Autodesk Fusion 360 part; units mm, degrees
(part 2 of 2)
  line L933 (25.5948, 17.0334) -> (24.794, 17.0334)
  line L934 (24.794, 17.0334) -> (24.794, 22.8334)
  line L935 (24.794, 22.8334) -> (25.5948, 22.8334)
  line L936 (25.5948, 22.8334) -> (25.5948, 25.9326)
  line L937 (25.5948, 25.9326) -> (24.794, 25.9326)
  line L938 (24.794, 25.9326) -> (24.794, 26.9331)
  line L939 (24.794, 26.9331) -> (10.7947, 26.9331)
  line L940 (29.8447, 26.9331) -> (29.8447, 25.9326)
  line L941 (29.8447, 25.9326) -> (29.0439, 25.9326)
  line L942 (29.0439, 25.9326) -> (29.0439, 22.8334)
  line L943 (29.0439, 22.8334) -> (29.8447, 22.8334)
  line L944 (29.8447, 22.8334) -> (29.8447, 17.0334)
  line L945 (29.8447, 17.0334) -> (29.0439, 17.0334)
  line L946 (29.0439, 17.0334) -> (29.0439, 13.9328)
  line L947 (29.0439, 13.9328) -> (29.8447, 13.9328)
  line L948 (29.8447, 13.9328) -> (29.8447, 12.9338)
  line L949 (29.8447, 12.9338) -> (43.844, 12.9338)
  line L950 (43.844, 12.9338) -> (43.844, 13.9328)
  line L951 (43.844, 13.9328) -> (44.645, 13.9328)
  line L952 (44.645, 13.9328) -> (44.645, 17.0334)
  line L953 (44.645, 17.0334) -> (43.844, 17.0334)
  line L954 (43.844, 17.0334) -> (43.844, 22.8334)
  line L955 (43.844, 22.8334) -> (44.645, 22.8334)
  line L956 (44.645, 22.8334) -> (44.645, 25.9326)
  line L957 (44.645, 25.9326) -> (43.844, 25.9326)
  line L958 (43.844, 25.9326) -> (43.844, 26.9331)
  line L959 (43.844, 26.9331) -> (29.8447, 26.9331)
  line L960 (48.895, 26.9331) -> (48.895, 25.9326)
  line L961 (48.895, 25.9326) -> (48.094, 25.9326)
  line L962 (48.094, 25.9326) -> (48.094, 22.8334)
  line L963 (48.094, 22.8334) -> (48.895, 22.8334)
  line L964 (48.895, 22.8334) -> (48.895, 17.0334)
  line L965 (48.895, 17.0334) -> (48.094, 17.0334)
  line L966 (48.094, 17.0334) -> (48.094, 13.9328)
  line L967 (48.094, 13.9328) -> (48.895, 13.9328)
  line L968 (48.895, 13.9328) -> (48.895, 12.9338)
  line L969 (48.895, 12.9338) -> (62.894, 12.9338)
  line L970 (62.894, 12.9338) -> (62.894, 13.9328)
  line L971 (62.894, 13.9328) -> (63.695, 13.9328)
  line L972 (63.695, 13.9328) -> (63.695, 17.0334)
  line L973 (63.695, 17.0334) -> (62.894, 17.0334)
  line L974 (62.894, 17.0334) -> (62.894, 22.8334)
  line L975 (62.894, 22.8334) -> (63.695, 22.8334)
  line L976 (63.695, 22.8334) -> (63.695, 25.9326)
  line L977 (63.695, 25.9326) -> (62.894, 25.9326)
  line L978 (62.894, 25.9326) -> (62.894, 26.9331)
  line L979 (62.894, 26.9331) -> (48.895, 26.9331)
  line L980 (67.945, 26.9331) -> (67.945, 25.9326)
  line L981 (67.945, 25.9326) -> (67.144, 25.9326)
  line L982 (67.144, 25.9326) -> (67.144, 22.8334)
  line L983 (67.144, 22.8334) -> (67.945, 22.8334)
  line L984 (67.945, 22.8334) -> (67.945, 17.0334)
  line L985 (67.945, 17.0334) -> (67.144, 17.0334)
  line L986 (67.144, 17.0334) -> (67.144, 13.9328)
  line L987 (67.144, 13.9328) -> (67.945, 13.9328)
  line L988 (67.945, 13.9328) -> (67.945, 12.9338)
  line L989 (67.945, 12.9338) -> (81.944, 12.9338)
  line L990 (81.944, 12.9338) -> (81.944, 13.9328)
  line L991 (81.944, 13.9328) -> (82.745, 13.9328)
  line L992 (82.745, 13.9328) -> (82.745, 17.0334)
  line L993 (82.745, 17.0334) -> (81.944, 17.0334)
  line L994 (81.944, 17.0334) -> (81.944, 22.8334)
  line L995 (81.944, 22.8334) -> (82.745, 22.8334)
  line L996 (82.745, 22.8334) -> (82.745, 25.9326)
  line L997 (82.745, 25.9326) -> (81.944, 25.9326)
  line L998 (81.944, 25.9326) -> (81.944, 26.9331)
  line L999 (81.944, 26.9331) -> (67.945, 26.9331)
  line L1000 (86.995, 26.9331) -> (86.995, 25.9326)
  line L1001 (86.995, 25.9326) -> (86.194, 25.9326)
  line L1002 (86.194, 25.9326) -> (86.194, 22.8334)
  line L1003 (86.194, 22.8334) -> (86.995, 22.8334)
  line L1004 (86.995, 22.8334) -> (86.995, 17.0334)
  line L1005 (86.995, 17.0334) -> (86.194, 17.0334)
  line L1006 (86.194, 17.0334) -> (86.194, 13.9328)
  line L1007 (86.194, 13.9328) -> (86.995, 13.9328)
  line L1008 (86.995, 13.9328) -> (86.995, 12.9338)
  line L1009 (86.995, 12.9338) -> (100.994, 12.9338)
  line L1010 (100.994, 12.9338) -> (100.994, 13.9328)
  line L1011 (100.994, 13.9328) -> (101.795, 13.9328)
  line L1012 (101.795, 13.9328) -> (101.795, 17.0334)
  line L1013 (101.795, 17.0334) -> (100.994, 17.0334)
  line L1014 (100.994, 17.0334) -> (100.994, 22.8334)
  line L1015 (100.994, 22.8334) -> (101.795, 22.8334)
  line L1016 (101.795, 22.8334) -> (101.795, 25.9326)
  line L1017 (101.795, 25.9326) -> (100.994, 25.9326)
  line L1018 (100.994, 25.9326) -> (100.994, 26.9331)
  line L1019 (100.994, 26.9331) -> (86.995, 26.9331)
  line L1020 (106.045, 26.9331) -> (106.045, 25.9326)
  line L1021 (106.045, 25.9326) -> (105.244, 25.9326)
  line L1022 (105.244, 25.9326) -> (105.244, 22.8334)
  line L1023 (105.244, 22.8334) -> (106.045, 22.8334)
  line L1024 (106.045, 22.8334) -> (106.045, 17.0334)
  line L1025 (106.045, 17.0334) -> (105.244, 17.0334)
  line L1026 (105.244, 17.0334) -> (105.244, 13.9328)
  line L1027 (105.244, 13.9328) -> (106.045, 13.9328)
  line L1028 (106.045, 13.9328) -> (106.045, 12.9338)
  line L1029 (106.045, 12.9338) -> (120.044, 12.9338)
  line L1030 (120.044, 12.9338) -> (120.044, 13.9328)
  line L1031 (120.044, 13.9328) -> (120.845, 13.9328)
  line L1032 (120.845, 13.9328) -> (120.845, 17.0334)
  line L1033 (120.845, 17.0334) -> (120.044, 17.0334)
  line L1034 (120.044, 17.0334) -> (120.044, 22.8334)
  line L1035 (120.044, 22.8334) -> (120.845, 22.8334)
  line L1036 (120.845, 22.8334) -> (120.845, 25.9326)
  line L1037 (120.845, 25.9326) -> (120.044, 25.9326)
  line L1038 (120.044, 25.9326) -> (120.044, 26.9331)
  line L1039 (120.044, 26.9331) -> (106.045, 26.9331)
  line L1040 (125.095, 26.9331) -> (125.095, 25.9326)
  line L1041 (125.095, 25.9326) -> (124.294, 25.9326)
  line L1042 (124.294, 25.9326) -> (124.294, 22.8334)
  line L1043 (124.294, 22.8334) -> (125.095, 22.8334)
  line L1044 (125.095, 22.8334) -> (125.095, 17.0334)
  line L1045 (125.095, 17.0334) -> (124.294, 17.0334)
  line L1046 (124.294, 17.0334) -> (124.294, 13.9328)
  line L1047 (124.294, 13.9328) -> (125.095, 13.9328)
  line L1048 (125.095, 13.9328) -> (125.095, 12.9338)
  line L1049 (125.095, 12.9338) -> (139.094, 12.9338)
  line L1050 (139.094, 12.9338) -> (139.094, 13.9328)
  line L1051 (139.094, 13.9328) -> (139.895, 13.9328)
  line L1052 (139.895, 13.9328) -> (139.895, 17.0334)
  line L1053 (139.895, 17.0334) -> (139.094, 17.0334)
  line L1054 (139.094, 17.0334) -> (139.094, 22.8334)
  line L1055 (139.094, 22.8334) -> (139.895, 22.8334)
  line L1056 (139.895, 22.8334) -> (139.895, 25.9326)
  line L1057 (139.895, 25.9326) -> (139.094, 25.9326)
  line L1058 (139.094, 25.9326) -> (139.094, 26.9331)
  line L1059 (139.094, 26.9331) -> (125.095, 26.9331)
  line L1060 (144.145, 26.9331) -> (144.145, 25.9326)
  line L1061 (144.145, 25.9326) -> (143.344, 25.9326)
  line L1062 (143.344, 25.9326) -> (143.344, 22.8334)
  line L1063 (143.344, 22.8334) -> (144.145, 22.8334)
  line L1064 (144.145, 22.8334) -> (144.145, 17.0334)
  line L1065 (144.145, 17.0334) -> (143.344, 17.0334)
  line L1066 (143.344, 17.0334) -> (143.344, 13.9328)
  line L1067 (143.344, 13.9328) -> (144.145, 13.9328)
  line L1068 (144.145, 13.9328) -> (144.145, 12.9338)
  line L1069 (144.145, 12.9338) -> (158.144, 12.9338)
  line L1070 (158.144, 12.9338) -> (158.144, 13.9328)
  line L1071 (158.144, 13.9328) -> (158.945, 13.9328)
  line L1072 (158.945, 13.9328) -> (158.945, 17.0334)
  line L1073 (158.945, 17.0334) -> (158.144, 17.0334)
  line L1074 (158.144, 17.0334) -> (158.144, 22.8334)
  line L1075 (158.144, 22.8334) -> (158.945, 22.8334)
  line L1076 (158.945, 22.8334) -> (158.945, 25.9326)
  line L1077 (158.945, 25.9326) -> (158.144, 25.9326)
  line L1078 (158.144, 25.9326) -> (158.144, 26.9331)
  line L1079 (158.144, 26.9331) -> (144.145, 26.9331)
  line L1080 (163.195, 26.9331) -> (163.195, 25.9326)
  line L1081 (163.195, 25.9326) -> (162.394, 25.9326)
  line L1082 (162.394, 25.9326) -> (162.394, 22.8334)
  line L1083 (162.394, 22.8334) -> (163.195, 22.8334)
  line L1084 (163.195, 22.8334) -> (163.195, 17.0334)
  line L1085 (163.195, 17.0334) -> (162.394, 17.0334)
  line L1086 (162.394, 17.0334) -> (162.394, 13.9328)
  line L1087 (162.394, 13.9328) -> (163.195, 13.9328)
  line L1088 (163.195, 13.9328) -> (163.195, 12.9338)
  line L1089 (163.195, 12.9338) -> (177.194, 12.9338)
  line L1090 (177.194, 12.9338) -> (177.194, 13.9328)
  line L1091 (177.194, 13.9328) -> (177.995, 13.9328)
  line L1092 (177.995, 13.9328) -> (177.995, 17.0334)
  line L1093 (177.995, 17.0334) -> (177.194, 17.0334)
  line L1094 (177.194, 17.0334) -> (177.194, 22.8334)
  line L1095 (177.194, 22.8334) -> (177.995, 22.8334)
  line L1096 (177.995, 22.8334) -> (177.995, 25.9326)
  line L1097 (177.995, 25.9326) -> (177.194, 25.9326)
  line L1098 (177.194, 25.9326) -> (177.194, 26.9331)
  line L1099 (177.194, 26.9331) -> (163.195, 26.9331)
  line L1100 (182.245, 26.9331) -> (182.245, 25.9326)
  line L1101 (182.245, 25.9326) -> (181.444, 25.9326)
  line L1102 (181.444, 25.9326) -> (181.444, 22.8334)
  line L1103 (181.444, 22.8334) -> (182.245, 22.8334)
  line L1104 (182.245, 22.8334) -> (182.245, 17.0334)
  line L1105 (182.245, 17.0334) -> (181.444, 17.0334)
  line L1106 (181.444, 17.0334) -> (181.444, 13.9328)
  line L1107 (181.444, 13.9328) -> (182.245, 13.9328)
  line L1108 (182.245, 13.9328) -> (182.245, 12.9338)
  line L1109 (182.245, 12.9338) -> (196.244, 12.9338)
  line L1110 (196.244, 12.9338) -> (196.244, 13.9328)
  line L1111 (196.244, 13.9328) -> (197.045, 13.9328)
  line L1112 (197.045, 13.9328) -> (197.045, 17.0334)
  line L1113 (197.045, 17.0334) -> (196.244, 17.0334)
  line L1114 (196.244, 17.0334) -> (196.244, 22.8334)
  line L1115 (196.244, 22.8334) -> (197.045, 22.8334)
  line L1116 (197.045, 22.8334) -> (197.045, 25.9326)
  line L1117 (197.045, 25.9326) -> (196.244, 25.9326)
  line L1118 (196.244, 25.9326) -> (196.244, 26.9331)
  line L1119 (196.244, 26.9331) -> (182.245, 26.9331)
  line L1120 (206.057, 26.9331) -> (206.057, 25.9326)
  line L1121 (206.057, 25.9326) -> (205.256, 25.9326)
  line L1122 (205.256, 25.9326) -> (205.256, 22.8334)
  line L1123 (205.256, 22.8334) -> (206.057, 22.8334)
  line L1124 (206.057, 22.8334) -> (206.057, 17.0334)
  line L1125 (206.057, 17.0334) -> (205.256, 17.0334)
  line L1126 (205.256, 17.0334) -> (205.256, 13.9328)
  line L1127 (205.256, 13.9328) -> (206.057, 13.9328)
  line L1128 (206.057, 13.9328) -> (206.057, 12.9338)
  line L1129 (206.057, 12.9338) -> (220.057, 12.9338)
  line L1130 (220.057, 12.9338) -> (220.057, 13.9328)
  line L1131 (220.057, 13.9328) -> (220.856, 13.9328)
  line L1132 (220.856, 13.9328) -> (220.856, 17.0334)
  line L1133 (220.856, 17.0334) -> (220.057, 17.0334)
  line L1134 (220.057, 17.0334) -> (220.057, 22.8334)
  line L1135 (220.057, 22.8334) -> (220.856, 22.8334)
  line L1136 (220.856, 22.8334) -> (220.856, 25.9326)
  line L1137 (220.856, 25.9326) -> (220.057, 25.9326)
  line L1138 (220.057, 25.9326) -> (220.057, 26.9331)
  line L1139 (220.057, 26.9331) -> (206.057, 26.9331)
  line L1140 (229.87, 26.9331) -> (229.87, 25.9326)
  line L1141 (229.87, 25.9326) -> (229.069, 25.9326)
  line L1142 (229.069, 25.9326) -> (229.069, 22.8334)
  line L1143 (229.069, 22.8334) -> (229.87, 22.8334)
  line L1144 (229.87, 22.8334) -> (229.87, 17.0334)
  line L1145 (229.87, 17.0334) -> (229.069, 17.0334)
  line L1146 (229.069, 17.0334) -> (229.069, 13.9328)
  line L1147 (229.069, 13.9328) -> (229.87, 13.9328)
  line L1148 (229.87, 13.9328) -> (229.87, 12.9338)
  line L1149 (229.87, 12.9338) -> (243.869, 12.9338)
  line L1150 (243.869, 12.9338) -> (243.869, 13.9328)
  line L1151 (243.869, 13.9328) -> (244.67, 13.9328)
  line L1152 (244.67, 13.9328) -> (244.67, 17.0334)
  line L1153 (244.67, 17.0334) -> (243.869, 17.0334)
  line L1154 (243.869, 17.0334) -> (243.869, 22.8334)
  line L1155 (243.869, 22.8334) -> (244.67, 22.8334)
  line L1156 (244.67, 22.8334) -> (244.67, 25.9326)
  line L1157 (244.67, 25.9326) -> (243.869, 25.9326)
  line L1158 (243.869, 25.9326) -> (243.869, 26.9331)
  line L1159 (243.869, 26.9331) -> (229.87, 26.9331)
  line L1160 (201.295, 45.9831) -> (201.295, 44.9826)
  line L1161 (201.295, 44.9826) -> (200.494, 44.9826)
  line L1162 (200.494, 44.9826) -> (200.494, 41.8834)
  line L1163 (200.494, 41.8834) -> (201.295, 41.8834)
  line L1164 (201.295, 41.8834) -> (201.295, 41.2826)
  line L1165 (201.295, 41.2826) -> (199.769, 41.2826)
  line L1166 (199.769, 41.2826) -> (199.769, 44.5127)
  line L1167 (199.769, 44.5127) -> (193.02, 44.5127)
  line L1168 (193.02, 44.5127) -> (193.02, 41.2826)
  line L1169 (193.02, 41.2826) -> (192.194, 41.2826)
  line L1170 (192.194, 41.2826) -> (192.194, 38.4837)
  line L1171 (192.194, 38.4837) -> (193.02, 38.4837)
  line L1172 (193.02, 38.4837) -> (193.02, 32.2138)
  line L1173 (193.02, 32.2138) -> (194.743, 32.2138)
  line L1174 (194.743, 32.2138) -> (194.743, 31.0136)
  line L1175 (194.743, 31.0136) -> (198.044, 31.0136)
  line L1176 (198.044, 31.0136) -> (198.044, 32.2138)
  line L1177 (198.044, 32.2138) -> (199.769, 32.2138)
  line L1178 (199.769, 32.2138) -> (199.769, 36.6828)
  line L1179 (199.769, 36.6828) -> (201.295, 36.6828)
  line L1180 (201.295, 36.6828) -> (201.295, 36.0834)
  line L1181 (201.295, 36.0834) -> (200.494, 36.0834)
  line L1182 (200.494, 36.0834) -> (200.494, 32.9828)
  line L1183 (200.494, 32.9828) -> (201.295, 32.9828)
  line L1184 (201.295, 32.9828) -> (201.295, 31.9838)
  line L1185 (201.295, 31.9838) -> (215.294, 31.9838)
  line L1186 (215.294, 31.9838) -> (215.294, 32.9828)
  line L1187 (215.294, 32.9828) -> (216.095, 32.9828)
  line L1188 (216.095, 32.9828) -> (216.095, 36.0834)
  line L1189 (216.095, 36.0834) -> (215.294, 36.0834)
  line L1190 (215.294, 36.0834) -> (215.294, 36.6828)
  line L1191 (215.294, 36.6828) -> (216.82, 36.6828)
  line L1192 (216.82, 36.6828) -> (216.82, 32.2138)
  line L1193 (216.82, 32.2138) -> (218.545, 32.2138)
  line L1194 (218.545, 32.2138) -> (218.545, 31.0136)
  line L1195 (218.545, 31.0136) -> (221.844, 31.0136)
  line L1196 (221.844, 31.0136) -> (221.844, 32.2138)
  line L1197 (221.844, 32.2138) -> (223.569, 32.2138)
  line L1198 (223.569, 32.2138) -> (223.569, 38.4837)
  line L1199 (223.569, 38.4837) -> (224.395, 38.4837)
  line L1200 (224.395, 38.4837) -> (224.395, 41.2826)
  line L1201 (224.395, 41.2826) -> (223.569, 41.2826)
  line L1202 (223.569, 41.2826) -> (223.569, 44.5127)
  line L1203 (223.569, 44.5127) -> (216.82, 44.5127)
  line L1204 (216.82, 44.5127) -> (216.82, 41.2826)
  line L1205 (216.82, 41.2826) -> (215.294, 41.2826)
  line L1206 (215.294, 41.2826) -> (215.294, 41.8834)
  line L1207 (215.294, 41.8834) -> (216.095, 41.8834)
  line L1208 (216.095, 41.8834) -> (216.095, 44.9826)
  line L1209 (216.095, 44.9826) -> (215.294, 44.9826)
  line L1210 (215.294, 44.9826) -> (215.294, 45.9831)
  line L1211 (215.294, 45.9831) -> (201.295, 45.9831)
  line L1212 (-55.8803, 45.9831) -> (-55.8803, 44.9826)
  line L1213 (-55.8803, 44.9826) -> (-56.681, 44.9826)
  line L1214 (-56.681, 44.9826) -> (-56.681, 41.8834)
  line L1215 (-56.681, 41.8834) -> (-55.8803, 41.8834)
  line L1216 (-55.8803, 41.8834) -> (-55.8803, 36.0834)
  line L1217 (-55.8803, 36.0834) -> (-56.681, 36.0834)
  line L1218 (-56.681, 36.0834) -> (-56.681, 32.9828)
  line L1219 (-56.681, 32.9828) -> (-55.8803, 32.9828)
  line L1220 (-55.8803, 32.9828) -> (-55.8803, 31.9838)
  line L1221 (-55.8803, 31.9838) -> (-41.8808, 31.9838)
  line L1222 (-41.8808, 31.9838) -> (-41.8808, 32.9828)
  line L1223 (-41.8808, 32.9828) -> (-41.0802, 32.9828)
  line L1224 (-41.0802, 32.9828) -> (-41.0802, 36.0834)
  line L1225 (-41.0802, 36.0834) -> (-41.8808, 36.0834)
  line L1226 (-41.8808, 36.0834) -> (-41.8808, 41.8834)
  line L1227 (-41.8808, 41.8834) -> (-41.0802, 41.8834)
  line L1228 (-41.0802, 41.8834) -> (-41.0802, 44.9826)
  line L1229 (-41.0802, 44.9826) -> (-41.8808, 44.9826)
  line L1230 (-41.8808, 44.9826) -> (-41.8808, 45.9831)
  line L1231 (-41.8808, 45.9831) -> (-55.8803, 45.9831)
  line L1232 (-36.8303, 45.9831) -> (-36.8303, 44.9826)
  line L1233 (-36.8303, 44.9826) -> (-37.631, 44.9826)
  line L1234 (-37.631, 44.9826) -> (-37.631, 41.8834)
  line L1235 (-37.631, 41.8834) -> (-36.8303, 41.8834)
  line L1236 (-36.8303, 41.8834) -> (-36.8303, 36.0834)
  line L1237 (-36.8303, 36.0834) -> (-37.631, 36.0834)
  line L1238 (-37.631, 36.0834) -> (-37.631, 32.9828)
  line L1239 (-37.631, 32.9828) -> (-36.8303, 32.9828)
  line L1240 (-36.8303, 32.9828) -> (-36.8303, 31.9838)
  line L1241 (-36.8303, 31.9838) -> (-22.831, 31.9838)
  line L1242 (-22.831, 31.9838) -> (-22.831, 32.9828)
  line L1243 (-22.831, 32.9828) -> (-22.0302, 32.9828)
  line L1244 (-22.0302, 32.9828) -> (-22.0302, 36.0834)
  line L1245 (-22.0302, 36.0834) -> (-22.831, 36.0834)
  line L1246 (-22.831, 36.0834) -> (-22.831, 41.8834)
  line L1247 (-22.831, 41.8834) -> (-22.0302, 41.8834)
  line L1248 (-22.0302, 41.8834) -> (-22.0302, 44.9826)
  line L1249 (-22.0302, 44.9826) -> (-22.831, 44.9826)
  line L1250 (-22.831, 44.9826) -> (-22.831, 45.9831)
  line L1251 (-22.831, 45.9831) -> (-36.8303, 45.9831)
  line L1252 (-17.7803, 45.9831) -> (-17.7803, 44.9826)
  line L1253 (-17.7803, 44.9826) -> (-18.5811, 44.9826)
  line L1254 (-18.5811, 44.9826) -> (-18.5811, 41.8834)
  line L1255 (-18.5811, 41.8834) -> (-17.7803, 41.8834)
  line L1256 (-17.7803, 41.8834) -> (-17.7803, 36.0834)
  line L1257 (-17.7803, 36.0834) -> (-18.5811, 36.0834)
  line L1258 (-18.5811, 36.0834) -> (-18.5811, 32.9828)
  line L1259 (-18.5811, 32.9828) -> (-17.7803, 32.9828)
  line L1260 (-17.7803, 32.9828) -> (-17.7803, 31.9838)
  line L1261 (-17.7803, 31.9838) -> (-3.781, 31.9838)
  line L1262 (-3.781, 31.9838) -> (-3.781, 32.9828)
  line L1263 (-3.781, 32.9828) -> (-2.9802, 32.9828)
  line L1264 (-2.9802, 32.9828) -> (-2.9802, 36.0834)
  line L1265 (-2.9802, 36.0834) -> (-3.781, 36.0834)
  line L1266 (-3.781, 36.0834) -> (-3.781, 41.8834)
  line L1267 (-3.781, 41.8834) -> (-2.9802, 41.8834)
  line L1268 (-2.9802, 41.8834) -> (-2.9802, 44.9826)
  line L1269 (-2.9802, 44.9826) -> (-3.781, 44.9826)
  line L1270 (-3.781, 44.9826) -> (-3.781, 45.9831)
  line L1271 (-3.781, 45.9831) -> (-17.7803, 45.9831)
  line L1272 (1.2697, 45.9831) -> (1.2697, 44.9826)
  line L1273 (1.2697, 44.9826) -> (0.4689, 44.9826)
  line L1274 (0.4689, 44.9826) -> (0.4689, 41.8834)
  line L1275 (0.4689, 41.8834) -> (1.2697, 41.8834)
  line L1276 (1.2697, 41.8834) -> (1.2697, 36.0834)
  line L1277 (1.2697, 36.0834) -> (0.4689, 36.0834)
  line L1278 (0.4689, 36.0834) -> (0.4689, 32.9828)
  line L1279 (0.4689, 32.9828) -> (1.2697, 32.9828)
  line L1280 (1.2697, 32.9828) -> (1.2697, 31.9838)
  line L1281 (1.2697, 31.9838) -> (15.269, 31.9838)
  line L1282 (15.269, 31.9838) -> (15.269, 32.9828)
  line L1283 (15.269, 32.9828) -> (16.0698, 32.9828)
  line L1284 (16.0698, 32.9828) -> (16.0698, 36.0834)
  line L1285 (16.0698, 36.0834) -> (15.269, 36.0834)
  line L1286 (15.269, 36.0834) -> (15.269, 41.8834)
  line L1287 (15.269, 41.8834) -> (16.0698, 41.8834)
  line L1288 (16.0698, 41.8834) -> (16.0698, 44.9826)
  line L1289 (16.0698, 44.9826) -> (15.269, 44.9826)
  line L1290 (15.269, 44.9826) -> (15.269, 45.9831)
  line L1291 (15.269, 45.9831) -> (1.2697, 45.9831)
  line L1292 (20.3197, 45.9831) -> (20.3197, 44.9826)
  line L1293 (20.3197, 44.9826) -> (19.5189, 44.9826)
  line L1294 (19.5189, 44.9826) -> (19.5189, 41.8834)
  line L1295 (19.5189, 41.8834) -> (20.3197, 41.8834)
  line L1296 (20.3197, 41.8834) -> (20.3197, 36.0834)
  line L1297 (20.3197, 36.0834) -> (19.5189, 36.0834)
  line L1298 (19.5189, 36.0834) -> (19.5189, 32.9828)
  line L1299 (19.5189, 32.9828) -> (20.3197, 32.9828)
  line L1300 (20.3197, 32.9828) -> (20.3197, 31.9838)
  line L1301 (20.3197, 31.9838) -> (34.319, 31.9838)
  line L1302 (34.319, 31.9838) -> (34.319, 32.9828)
  line L1303 (34.319, 32.9828) -> (35.1184, 32.9828)
  line L1304 (35.1184, 32.9828) -> (35.1184, 36.0834)
  line L1305 (35.1184, 36.0834) -> (34.319, 36.0834)
  line L1306 (34.319, 36.0834) -> (34.319, 41.8834)
  line L1307 (34.319, 41.8834) -> (35.1184, 41.8834)
  line L1308 (35.1184, 41.8834) -> (35.1184, 44.9826)
  line L1309 (35.1184, 44.9826) -> (34.319, 44.9826)
  line L1310 (34.319, 44.9826) -> (34.319, 45.9831)
  line L1311 (34.319, 45.9831) -> (20.3197, 45.9831)
  line L1312 (39.3683, 45.9831) -> (39.3683, 44.9826)
  line L1313 (39.3683, 44.9826) -> (38.5689, 44.9826)
  line L1314 (38.5689, 44.9826) -> (38.5689, 41.8834)
  line L1315 (38.5689, 41.8834) -> (39.3683, 41.8834)
  line L1316 (39.3683, 41.8834) -> (39.3683, 36.0834)
  line L1317 (39.3683, 36.0834) -> (38.5689, 36.0834)
  line L1318 (38.5689, 36.0834) -> (38.5689, 32.9828)
  line L1319 (38.5689, 32.9828) -> (39.3683, 32.9828)
  line L1320 (39.3683, 32.9828) -> (39.3683, 31.9838)
  line L1321 (39.3683, 31.9838) -> (53.369, 31.9838)
  line L1322 (53.369, 31.9838) -> (53.369, 32.9828)
  line L1323 (53.369, 32.9828) -> (54.168, 32.9828)
  line L1324 (54.168, 32.9828) -> (54.168, 36.0834)
  line L1325 (54.168, 36.0834) -> (53.369, 36.0834)
  line L1326 (53.369, 36.0834) -> (53.369, 41.8834)
  line L1327 (53.369, 41.8834) -> (54.168, 41.8834)
  line L1328 (54.168, 41.8834) -> (54.168, 44.9826)
  line L1329 (54.168, 44.9826) -> (53.369, 44.9826)
  line L1330 (53.369, 44.9826) -> (53.369, 45.9831)
  line L1331 (53.369, 45.9831) -> (39.3683, 45.9831)
  line L1332 (58.418, 45.9831) -> (58.418, 44.9826)
  line L1333 (58.418, 44.9826) -> (57.619, 44.9826)
  line L1334 (57.619, 44.9826) -> (57.619, 41.8834)
  line L1335 (57.619, 41.8834) -> (58.418, 41.8834)
  line L1336 (58.418, 41.8834) -> (58.418, 36.0834)
  line L1337 (58.418, 36.0834) -> (57.619, 36.0834)
  line L1338 (57.619, 36.0834) -> (57.619, 32.9828)
  line L1339 (57.619, 32.9828) -> (58.418, 32.9828)
  line L1340 (58.418, 32.9828) -> (58.418, 31.9838)
  line L1341 (58.418, 31.9838) -> (72.419, 31.9838)
  line L1342 (72.419, 31.9838) -> (72.419, 32.9828)
  line L1343 (72.419, 32.9828) -> (73.22, 32.9828)
  line L1344 (73.22, 32.9828) -> (73.22, 36.0834)
  line L1345 (73.22, 36.0834) -> (72.419, 36.0834)
  line L1346 (72.419, 36.0834) -> (72.419, 41.8834)
  line L1347 (72.419, 41.8834) -> (73.22, 41.8834)
  line L1348 (73.22, 41.8834) -> (73.22, 44.9826)
  line L1349 (73.22, 44.9826) -> (72.419, 44.9826)
  line L1350 (72.419, 44.9826) -> (72.419, 45.9831)
  line L1351 (72.419, 45.9831) -> (58.418, 45.9831)
  line L1352 (77.47, 45.9831) -> (77.47, 44.9826)
  line L1353 (77.47, 44.9826) -> (76.669, 44.9826)
  line L1354 (76.669, 44.9826) -> (76.669, 41.8834)
  line L1355 (76.669, 41.8834) -> (77.47, 41.8834)
  line L1356 (77.47, 41.8834) -> (77.47, 36.0834)
  line L1357 (77.47, 36.0834) -> (76.669, 36.0834)
  line L1358 (76.669, 36.0834) -> (76.669, 32.9828)
  line L1359 (76.669, 32.9828) -> (77.47, 32.9828)
  line L1360 (77.47, 32.9828) -> (77.47, 31.9838)
  line L1361 (77.47, 31.9838) -> (91.469, 31.9838)
  line L1362 (91.469, 31.9838) -> (91.469, 32.9828)
  line L1363 (91.469, 32.9828) -> (92.27, 32.9828)
  line L1364 (92.27, 32.9828) -> (92.27, 36.0834)
  line L1365 (92.27, 36.0834) -> (91.469, 36.0834)
  line L1366 (91.469, 36.0834) -> (91.469, 41.8834)
  line L1367 (91.469, 41.8834) -> (92.27, 41.8834)
  line L1368 (92.27, 41.8834) -> (92.27, 44.9826)
  line L1369 (92.27, 44.9826) -> (91.469, 44.9826)
  line L1370 (91.469, 44.9826) -> (91.469, 45.9831)
  line L1371 (91.469, 45.9831) -> (77.47, 45.9831)
  line L1372 (96.52, 45.9831) -> (96.52, 44.9826)
  line L1373 (96.52, 44.9826) -> (95.719, 44.9826)
  line L1374 (95.719, 44.9826) -> (95.719, 41.8834)
  line L1375 (95.719, 41.8834) -> (96.52, 41.8834)
  line L1376 (96.52, 41.8834) -> (96.52, 36.0834)
  line L1377 (96.52, 36.0834) -> (95.719, 36.0834)
  line L1378 (95.719, 36.0834) -> (95.719, 32.9828)
  line L1379 (95.719, 32.9828) -> (96.52, 32.9828)
  line L1380 (96.52, 32.9828) -> (96.52, 31.9838)
  line L1381 (96.52, 31.9838) -> (110.519, 31.9838)
  line L1382 (110.519, 31.9838) -> (110.519, 32.9828)
  line L1383 (110.519, 32.9828) -> (111.32, 32.9828)
  line L1384 (111.32, 32.9828) -> (111.32, 36.0834)
  line L1385 (111.32, 36.0834) -> (110.519, 36.0834)
  line L1386 (110.519, 36.0834) -> (110.519, 41.8834)
  line L1387 (110.519, 41.8834) -> (111.32, 41.8834)
  line L1388 (111.32, 41.8834) -> (111.32, 44.9826)
  line L1389 (111.32, 44.9826) -> (110.519, 44.9826)
  line L1390 (110.519, 44.9826) -> (110.519, 45.9831)
  line L1391 (110.519, 45.9831) -> (96.52, 45.9831)
  line L1392 (115.57, 45.9831) -> (115.57, 44.9826)
  line L1393 (115.57, 44.9826) -> (114.769, 44.9826)
  line L1394 (114.769, 44.9826) -> (114.769, 41.8834)
  line L1395 (114.769, 41.8834) -> (115.57, 41.8834)
  line L1396 (115.57, 41.8834) -> (115.57, 36.0834)
  line L1397 (115.57, 36.0834) -> (114.769, 36.0834)
  line L1398 (114.769, 36.0834) -> (114.769, 32.9828)
  line L1399 (114.769, 32.9828) -> (115.57, 32.9828)
  line L1400 (115.57, 32.9828) -> (115.57, 31.9838)
  line L1401 (115.57, 31.9838) -> (129.569, 31.9838)
  line L1402 (129.569, 31.9838) -> (129.569, 32.9828)
  line L1403 (129.569, 32.9828) -> (130.37, 32.9828)
  line L1404 (130.37, 32.9828) -> (130.37, 36.0834)
  line L1405 (130.37, 36.0834) -> (129.569, 36.0834)
  line L1406 (129.569, 36.0834) -> (129.569, 41.8834)
  line L1407 (129.569, 41.8834) -> (130.37, 41.8834)
  line L1408 (130.37, 41.8834) -> (130.37, 44.9826)
  line L1409 (130.37, 44.9826) -> (129.569, 44.9826)
  line L1410 (129.569, 44.9826) -> (129.569, 45.9831)
  line L1411 (129.569, 45.9831) -> (115.57, 45.9831)
  line L1412 (134.62, 45.9831) -> (134.62, 44.9826)
  line L1413 (134.62, 44.9826) -> (133.819, 44.9826)
  line L1414 (133.819, 44.9826) -> (133.819, 41.8834)
  line L1415 (133.819, 41.8834) -> (134.62, 41.8834)
  line L1416 (134.62, 41.8834) -> (134.62, 36.0834)
  line L1417 (134.62, 36.0834) -> (133.819, 36.0834)
  line L1418 (133.819, 36.0834) -> (133.819, 32.9828)
  line L1419 (133.819, 32.9828) -> (134.62, 32.9828)
  line L1420 (134.62, 32.9828) -> (134.62, 31.9838)
  line L1421 (134.62, 31.9838) -> (148.619, 31.9838)
  line L1422 (148.619, 31.9838) -> (148.619, 32.9828)
  line L1423 (148.619, 32.9828) -> (149.42, 32.9828)
  line L1424 (149.42, 32.9828) -> (149.42, 36.0834)
  line L1425 (149.42, 36.0834) -> (148.619, 36.0834)
  line L1426 (148.619, 36.0834) -> (148.619, 41.8834)
  line L1427 (148.619, 41.8834) -> (149.42, 41.8834)
  line L1428 (149.42, 41.8834) -> (149.42, 44.9826)
  line L1429 (149.42, 44.9826) -> (148.619, 44.9826)
  line L1430 (148.619, 44.9826) -> (148.619, 45.9831)
  line L1431 (148.619, 45.9831) -> (134.62, 45.9831)
  line L1432 (153.67, 45.9831) -> (153.67, 44.9826)
  line L1433 (153.67, 44.9826) -> (152.869, 44.9826)
  line L1434 (152.869, 44.9826) -> (152.869, 41.8834)
  line L1435 (152.869, 41.8834) -> (153.67, 41.8834)
  line L1436 (153.67, 41.8834) -> (153.67, 36.0834)
  line L1437 (153.67, 36.0834) -> (152.869, 36.0834)
  line L1438 (152.869, 36.0834) -> (152.869, 32.9828)
  line L1439 (152.869, 32.9828) -> (153.67, 32.9828)
  line L1440 (153.67, 32.9828) -> (153.67, 31.9838)
  line L1441 (153.67, 31.9838) -> (167.669, 31.9838)
  line L1442 (167.669, 31.9838) -> (167.669, 32.9828)
  line L1443 (167.669, 32.9828) -> (168.47, 32.9828)
  line L1444 (168.47, 32.9828) -> (168.47, 36.0834)
  line L1445 (168.47, 36.0834) -> (167.669, 36.0834)
  line L1446 (167.669, 36.0834) -> (167.669, 41.8834)
  line L1447 (167.669, 41.8834) -> (168.47, 41.8834)
  line L1448 (168.47, 41.8834) -> (168.47, 44.9826)
  line L1449 (168.47, 44.9826) -> (167.669, 44.9826)
  line L1450 (167.669, 44.9826) -> (167.669, 45.9831)
  line L1451 (167.669, 45.9831) -> (153.67, 45.9831)
  line L1452 (172.72, 45.9831) -> (172.72, 44.9826)
  line L1453 (172.72, 44.9826) -> (171.919, 44.9826)
  line L1454 (171.919, 44.9826) -> (171.919, 41.8834)
  line L1455 (171.919, 41.8834) -> (172.72, 41.8834)
  line L1456 (172.72, 41.8834) -> (172.72, 36.0834)
  line L1457 (172.72, 36.0834) -> (171.919, 36.0834)
  line L1458 (171.919, 36.0834) -> (171.919, 32.9828)
  line L1459 (171.919, 32.9828) -> (172.72, 32.9828)
  line L1460 (172.72, 32.9828) -> (172.72, 31.9838)
  line L1461 (172.72, 31.9838) -> (186.719, 31.9838)
  line L1462 (186.719, 31.9838) -> (186.719, 32.9828)
  line L1463 (186.719, 32.9828) -> (187.52, 32.9828)
  line L1464 (187.52, 32.9828) -> (187.52, 36.0834)
  line L1465 (187.52, 36.0834) -> (186.719, 36.0834)
  line L1466 (186.719, 36.0834) -> (186.719, 41.8834)
  line L1467 (186.719, 41.8834) -> (187.52, 41.8834)
  line L1468 (187.52, 41.8834) -> (187.52, 44.9826)
  line L1469 (187.52, 44.9826) -> (186.719, 44.9826)
  line L1470 (186.719, 44.9826) -> (186.719, 45.9831)
  line L1471 (186.719, 45.9831) -> (172.72, 45.9831)
  line L1472 (229.87, 45.9831) -> (229.87, 44.9826)
  line L1473 (229.87, 44.9826) -> (229.069, 44.9826)
  line L1474 (229.069, 44.9826) -> (229.069, 41.8834)
  line L1475 (229.069, 41.8834) -> (229.87, 41.8834)
  line L1476 (229.87, 41.8834) -> (229.87, 36.0834)
  line L1477 (229.87, 36.0834) -> (229.069, 36.0834)
  line L1478 (229.069, 36.0834) -> (229.069, 32.9828)
  line L1479 (229.069, 32.9828) -> (229.87, 32.9828)
  line L1480 (229.87, 32.9828) -> (229.87, 31.9838)
  line L1481 (229.87, 31.9838) -> (243.869, 31.9838)
  line L1482 (243.869, 31.9838) -> (243.869, 32.9828)
  line L1483 (243.869, 32.9828) -> (244.67, 32.9828)
  line L1484 (244.67, 32.9828) -> (244.67, 36.0834)
  line L1485 (244.67, 36.0834) -> (243.869, 36.0834)
  line L1486 (243.869, 36.0834) -> (243.869, 41.8834)
  line L1487 (243.869, 41.8834) -> (244.67, 41.8834)
  line L1488 (244.67, 41.8834) -> (244.67, 44.9826)
  line L1489 (244.67, 44.9826) -> (243.869, 44.9826)
  line L1490 (243.869, 44.9826) -> (243.869, 45.9831)
  line L1491 (243.869, 45.9831) -> (229.87, 45.9831)
  dimension "d1" = 334
  dimension "d2" = 98
  constraint horizontal L0
  constraint vertical L1
  constraint horizontal L2
  constraint vertical L3
  measures "d1" distance of L0.start L0.end
  measures "d2" distance of L0.start L2.end
extrude "Extrude1" add sketch "Sketch1" along normal blind 1.5
sketch "Sketch2" plane through (0, 0, 0) normal (0, 0, 1) x (1, 0, 0)
  line L0 (-60, 50) -> (274, 50)
  line L1 (-60, -48) -> (-60, 50)
  circle A0 centre (-40, 31.5) radius 1.6
  line L2 (274, -48) -> (-60, -48)
  circle A1 centre (-35.15, -29) radius 1.6
  circle A2 centre (108, 10.5) radius 1.6
  circle A3 centre (108, -8) radius 1.6
  line L3 (274, 50) -> (274, -48)
  circle A4 centre (226.5, 31.4) radius 1.6
  circle A5 centre (227.4, -28.7) radius 1.6
  dimension "d8" = 3.2
  dimension "d12" = 3.2
  dimension "d17" = 3.2
  dimension "d20" = 3.2
  dimension "d24" = 3.2
  dimension "d28" = 3.2
  measures "d8" diameter of A0
  measures "d12" diameter of A1
  measures "d17" diameter of A2
  measures "d20" diameter of A3
  measures "d24" diameter of A4
  measures "d28" diameter of A5
extrude "Extrude2" cut sketch "Sketch2" along normal blind 2 contours A1
extrude "Extrude3" cut sketch "Sketch2" along normal blind 2 contours A0
extrude "Extrude4" cut sketch "Sketch2" along normal blind 2 contours A2
extrude "Extrude5" cut sketch "Sketch2" along normal blind 2 contours A3
extrude "Extrude6" cut sketch "Sketch2" along normal blind 2 contours A4
extrude "Extrude7" cut sketch "Sketch2" along normal blind 2 contours A5
